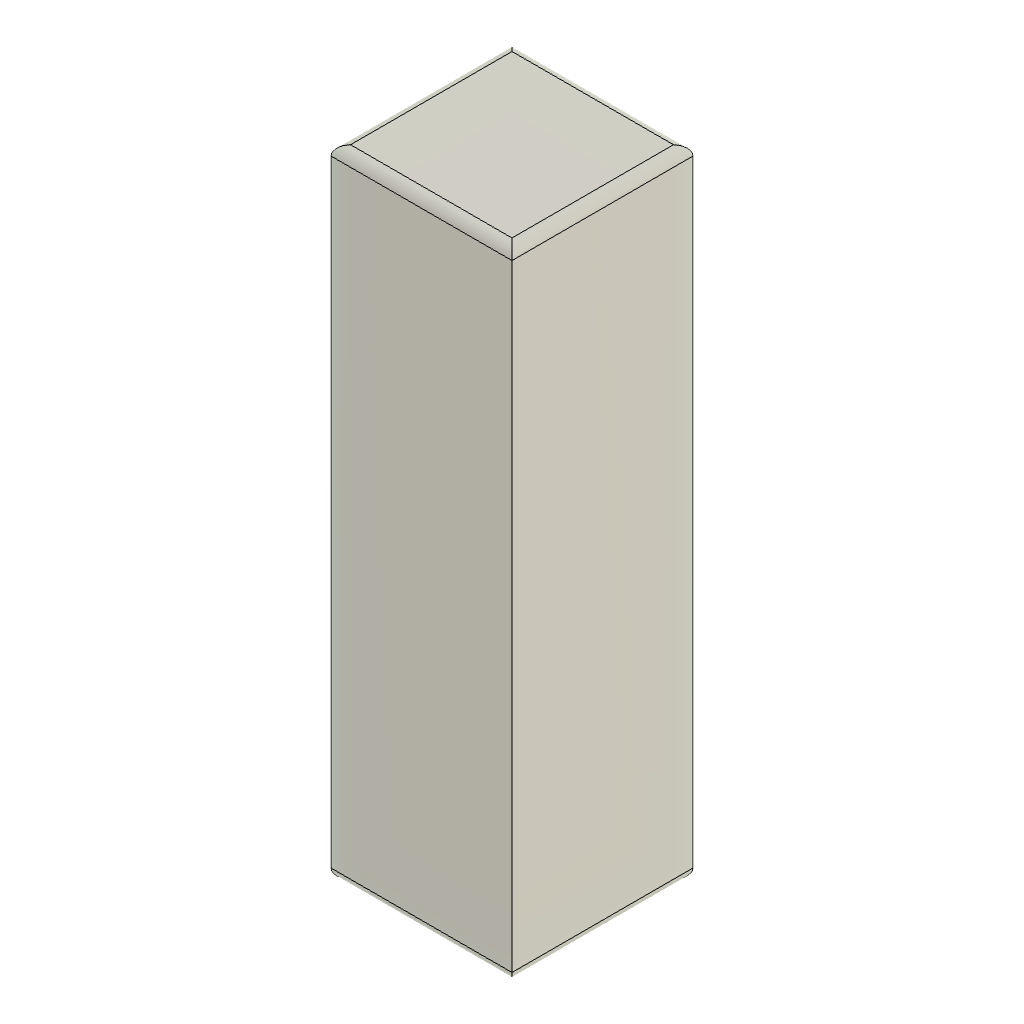
crank_inner_connector (Autodesk Fusion 360 design; units mm, degrees)
part number: 2026-10-03-17-44-13-974
Autodesk Fusion 360 part; units mm, degrees
sketch "Sketch1" plane through (0, 0, 0) normal (0, 0, 1) x (1, 0, 0)
  line L0 (3.7, -3.7) -> (-3.7, -3.7)
  line L1 (-3.7, -3.7) -> (-3.7, 3.7)
  line L2 (-3.7, 3.7) -> (3.7, 3.7)
  line L3 (3.7, 3.7) -> (3.7, -3.7)
  line L4 (3.7, -3.7) -> (-3.7, 3.7) construction
  line L5 (-3.7, -3.7) -> (3.7, 3.7) construction
  dimension "d1" = 7.4
  dimension "d2" = 7.4
  constraint horizontal L0
  constraint perpendicular L0 L1
  constraint parallel L0 L2
  constraint parallel L1 L3
  constraint coincident L4 origin
  constraint coincident L5 origin
  measures "d1" distance of L1.end L2.end
  measures "d2" distance of L0.end L1.end
extrude "Extrude1" add sketch "Sketch1" along normal blind 26
fillet "Fillet1" radius 0.4 8 edges at (0, -3.7, 26) (3.7, 0, 26) (0, 3.7, 26) (-3.7, 0, 26) (3.7, 0, 0) (0, 3.7, 0) (-3.7, 0, 0) (0, -3.7, 0)
